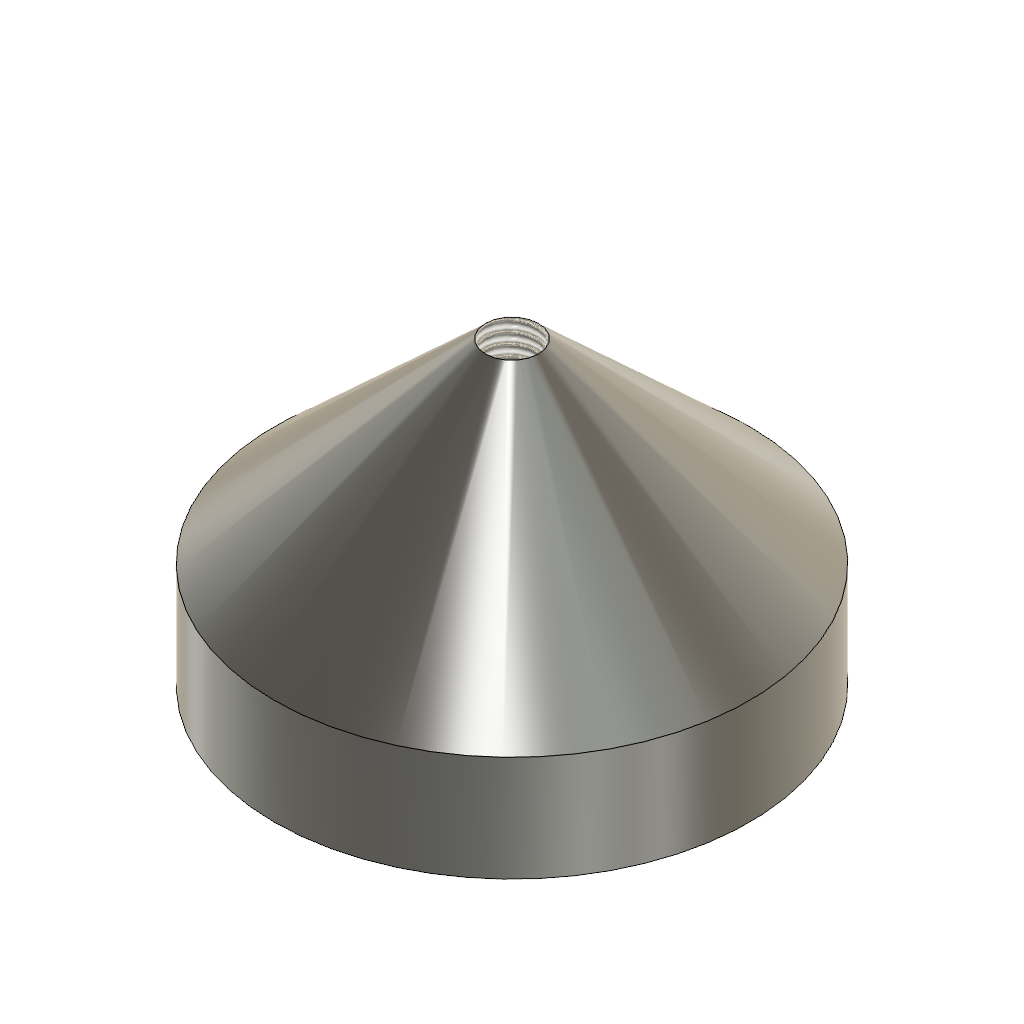
pad (Autodesk Fusion 360 design; units mm, degrees)
part number: 2026-10-15-14-46-52-154
Autodesk Fusion 360 part; units mm, degrees
sketch "Sketch1" plane through (0, 0, 0) normal (1, 0, 0) x (0, 1, 0)
  line L0 (0, 0) -> (22.5, 0)
  line L1 (22.5, 0) -> (22.5, 10)
  line L2 (0, 0) -> (0, 28)
  line L3 (3, 10) -> (3, 28)
  line L4 (3, 28) -> (22.5, 10)
  line L5 (3, 10) -> (0, 10)
  dimension "d1" = 22.5
  dimension "d2" = 10
  dimension "d3" = 28
  dimension "d4" = 19.5
  constraint coincident L0.start L2.start
  constraint horizontal L0
  constraint perpendicular L0 L1
  constraint perpendicular L0 L2
  constraint coincident L2 L5.end
  constraint perpendicular L2 L5
  measures "d1" distance of L0.start L0.end
  measures "d2" distance of L0.end L1.end
  measures "d3" distance of L0.start L2.end
  measures "d4" distance of L1.end L3.start
revolve "Revolve1" add sketch "Sketch1" angle 360 about axis through (0, 0, 0) along (0, 0, 1)
thread "Thread1" "ISO Metric profile 6.0 M6x1 M6x1 6H" major diameter 6.147 minor diameter 5.035 pitch 1 angle 60 resizes the face on face at (0.2987, 2.9851, 16)
